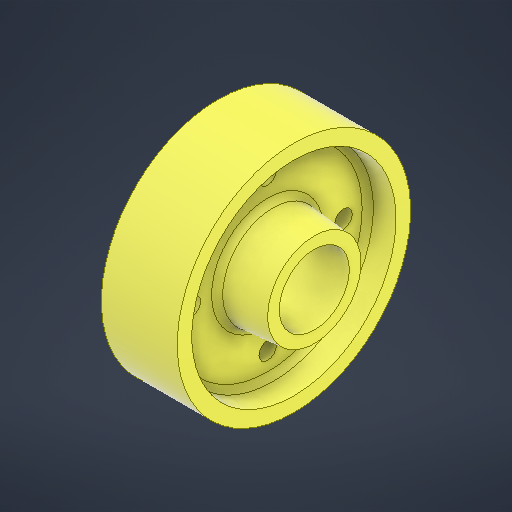
# Autodesk Inventor part: Roller
Saved by Autodesk Inventor 2026.3 (Build 303398000, 398)
## iProperties
Created: 2026-11-02
Part Number: Roller
Material: Steel, Alloy
Document SubType Name: Modeling
Designer: ADMIN
Density: 7.73 g/cm^3
Appearance: Smooth - Yellow
Author: ADMIN
Autodesk Inventor part; units mm, degrees
ref_plane "YZ Plane" through (0, 0, 0) normal (1, 0, 0) x (0, 1, 0)
ref_plane "XZ Plane" through (0, 0, 0) normal (0, 1, 0) x (-1, 0, 0)
ref_plane "XY Plane" through (0, 0, 0) normal (0, 0, 1) x (1, 0, 0)
sketch "Sketch1" plane through (0, 0, 0) normal (0, 0, 1) x (1, 0, 0)
  line L0 (-13, 40) -> (13, 40)
  line L1 (13, 40) -> (13, 35)
  line L2 (13, 35) -> (5.8257, 34.3723)
  line L3 (4, 32.3799) -> (4, 19.2325)
  line L4 (5.8257, 17.2401) -> (20, 16)
  line L5 (20, 16) -> (20, 12)
  line L6 (20, 12) -> (-20, 12)
  line L7 (-20, 12) -> (-20, 16)
  line L8 (-20, 16) -> (-5.8257, 17.2401)
  line L9 (-4, 19.2325) -> (-4, 32.3799)
  line L10 (-5.8257, 34.3723) -> (-13, 35)
  line L11 (-13, 35) -> (-13, 40)
  line L12 (0, 40) -> (0, 0)
  arc A0 (5.8257, 34.3723) -> (4, 32.3799) centre (6, 32.3799) ccw
  arc A1 (-4, 32.3799) -> (-5.8257, 34.3723) centre (-6, 32.3799) ccw
  line L13 (-10, 0) -> (10, 0)
  arc A2 (-5.8257, 17.2401) -> (-4, 19.2325) centre (-6, 19.2325) ccw
  arc A3 (4, 19.2325) -> (5.8257, 17.2401) centre (6, 19.2325) ccw
  dimension "d5" = 5
  dimension "d6" = 5
  dimension "d7" = 2
  dimension "d9" = 24
  dimension "d10" = 20
  dimension "d11" = 2
  dimension "d12" = 32
  dimension "d13" = 80
  dimension "d14" = 70
  dimension "d15" = 40
  dimension "d16" = 26
  dimension "d17" = 8
  constraints: 28 end point, 8 point on circle, 8 tangent, 4 centre point, 4 parallel, 3 perpendicular, 3 symmetric about line, 2 equal radius, 2 horizontal, 2 midpoint, 1 coincident, 1 vertical, 3 other
  measures "d5" angle of L6 L4
  measures "d6" angle of L0 L2
  measures "d7" radius of A0
  measures "d9" diameter of L6 L13
  measures "d10" distance of L13.start L13.end
  measures "d11" radius of A2
  measures "d12" diameter of L7.end L13
  measures "d13" diameter of L0 L13
  measures "d14" diameter of L10.end L13
  measures "d15" distance between parallel lines of L5 L7
  measures "d16" distance between parallel lines of L1 L11
  measures "d17" distance between parallel lines of L3 L9
revolve "Revolution1" add sketch "Sketch1" angle 360 about axis through (-10, 0, 0) along (1, 0, 0)
sketch "Sketch3" plane through (4, 0, 0) normal (1, 0, 0) x (0, 0, -1)
  point P0 (0, 0)
  point P1 (0, 26)
  point P2 (-26, 0)
  point P3 (0, -26)
  point P4 (26, 0)
  dimension "d19" = 26
  dimension "d22" = 360
  constraints: 1 vertical alignment, 5 other
  measures "d19" distance of point (0, 0) point (0, 26)
hole "Hole1" at (4, 26, 0) at (4, 0, 26) at (4, -26, 0) at (4, 0, -26) direction (-1, 0, 0) diameter 6 end through all
body "Solid1"
